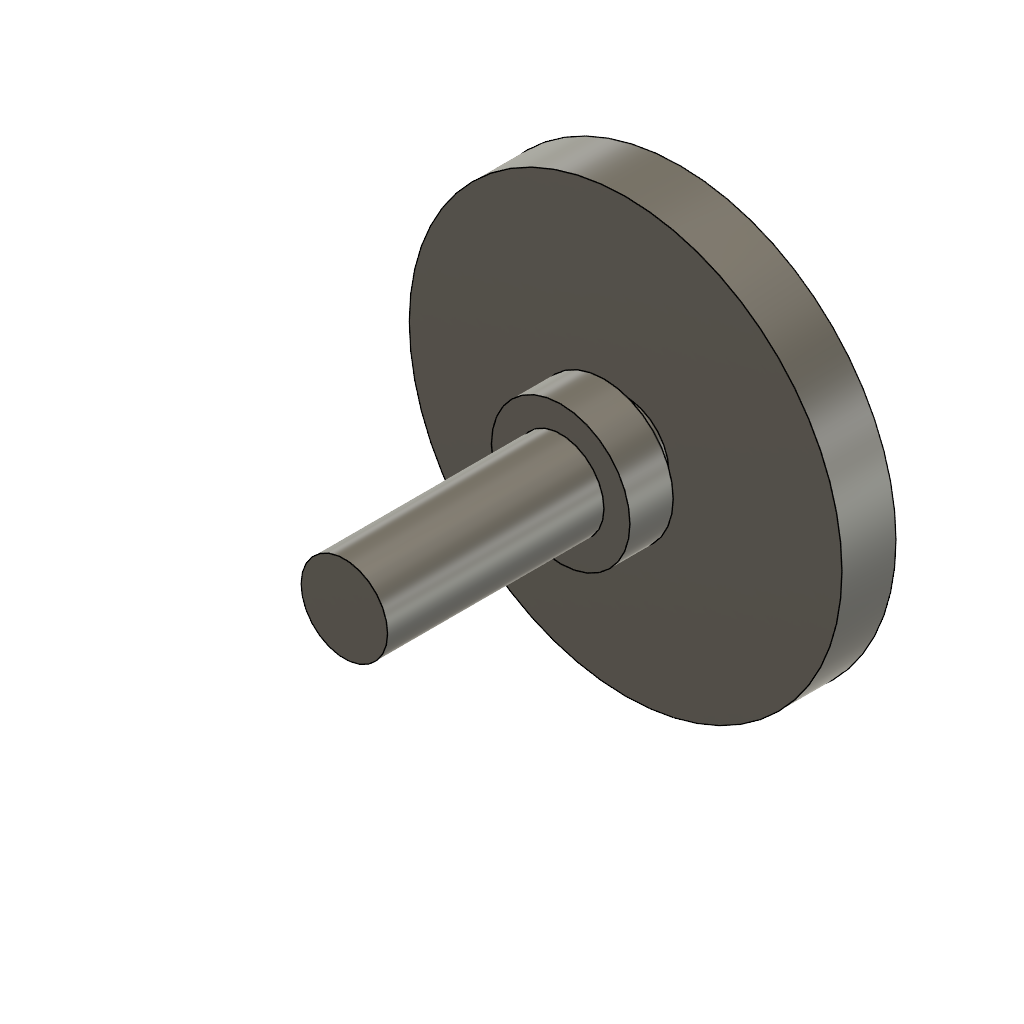
DRR_M1_levelling_foot (Autodesk Fusion 360 design; units mm, degrees)
part number: 2026-11-05-14-50-53-292
Autodesk Fusion 360 part; units mm, degrees
sketch "Sketch1" plane through (0, 0, 0) normal (0, 0, 1) x (1, 0, 0)
  circle A0 centre (300, 354) radius 40
  dimension "d2136" = 354
  dimension "d2137" = 80
  measures "d2136" vertical distance of origin A0.centre
  measures "d2137" diameter of A0
extrude "Extrude1" add sketch "Sketch1" along normal blind 10 from surface at 8
sketch "Sketch2" plane through (0, 0, 0) normal (0, 0, 1) x (1, 0, 0)
  circle A0 centre (300, 354) radius 8
  dimension "d2142" = 354
  dimension "d2143" = 16
  measures "d2142" vertical distance of origin A0.centre
  measures "d2143" diameter of A0
extrude "Extrude2" add sketch "Sketch2" along normal blind 52 from surface at 18
sketch "Sketch3" plane through (0, 0, 0) normal (0, 0, 1) x (1, 0, 0)
  circle A0 centre (300, 354) radius 12.8
  dimension "d2148" = 354
  dimension "d2149" = 25.6
  measures "d2148" vertical distance of origin A0.centre
  measures "d2149" diameter of A0
extrude "Extrude3" add sketch "Sketch3" along normal blind 8 from surface at 22
equation "d2135 = ( frame_inset )"
equation "d2136 = ( ( rail_cc / 2 ) )"
equation "d2137 = foot_pad_d"
equation "d2138 = foot_plate_t"
equation "d2139 = ( foot_plate_t + foot_pad_t ) - ( foot_plate_t )"
equation "d2141 = ( frame_inset )"
equation "d2142 = ( ( rail_cc / 2 ) )"
equation "d2143 = foot_stud_d"
equation "d2144 = foot_plate_t + foot_pad_t"
equation "d2145 = ( foot_h + 40 mm ) - ( foot_plate_t + foot_pad_t )"
equation "d2147 = ( frame_inset )"
equation "d2148 = ( ( rail_cc / 2 ) )"
equation "d2149 = 1.6 * foot_stud_d"
equation "d2150 = foot_h - 8 mm"
equation "d2151 = ( foot_h ) - ( foot_h - 8 mm )"
equation "body_width = 508 mm" comment "spec: body width, design value"
equation "side_clear = 25 mm" comment "spec: gap between body and cap each side"
equation "rail_gap = body_width + 2 * side_clear" comment "spec: inner gap between caps"
equation "cap_width = 150 mm" comment "spec"
equation "frame_inset = 300 mm" comment "spec: U-frame position from section end"
equation "rail_cc = rail_gap + cap_width" comment "derived: rail centre-to-centre"
equation "foot_h = 30 mm" comment "assumed: ground to frame underside"
equation "foot_plate_t = 8 mm" comment "assumed"
equation "foot_pad_d = 80 mm" comment "assumed"
equation "foot_pad_t = 10 mm" comment "assumed"
equation "foot_stud_d = 16 mm" comment "assumed: M16 levelling stud"
named bodies: "Foot R1"
